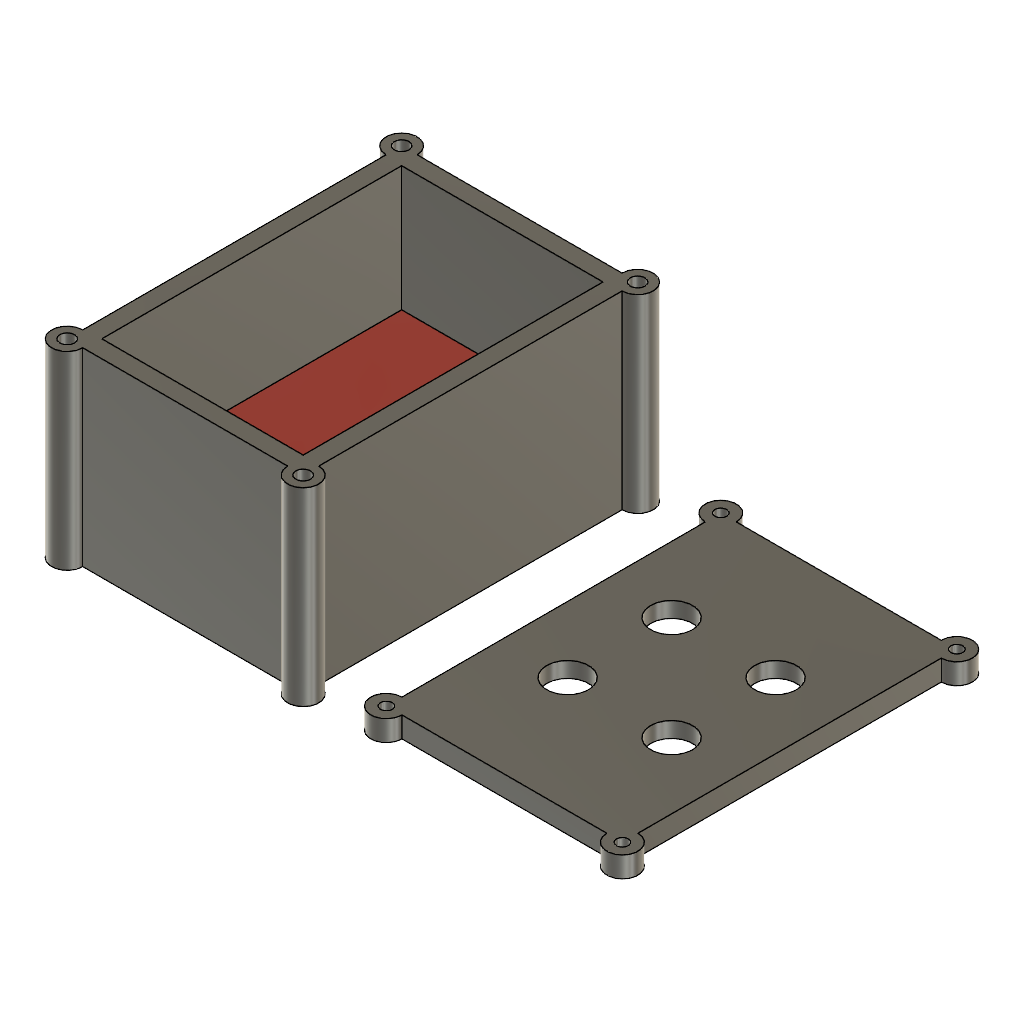
TP2 Caja (Autodesk Fusion 360 design; units mm, degrees)
Autodesk Fusion 360 part; units mm, degrees
sketch "Boceto1" plane through (0, 0, 0) normal (0, 0, 1) x (1, 0, 0)
  line L0 (0, 0) -> (56.1, 0)
  line L1 (56.1, 0) -> (56.1, 84.5)
  line L2 (56.1, 84.5) -> (0, 84.5)
  line L3 (0, 84.5) -> (0, 0)
  dimension "d1" = 56.1
  dimension "d2" = 84.5
  constraint horizontal L0
  constraint vertical L1
  constraint horizontal L2
  constraint vertical L3
  constraint coincident L0.start L3.end
  measures "d1" distance of L0.start L0.end
  measures "d2" distance of L0.start L2.end
extrude "Extruir1" add sketch "Boceto1" along normal blind 16.7 makes body 1
sketch "Boceto2" plane through (0, 0, 0) normal (0, 0, 1) x (1, 0, 0)
sketch "Boceto23" plane through (0, 0, 0) normal (0, 0, 1) x (1, 0, 0)
  line L0 (-6, -6) -> (62.1, -6)
  line L1 (62.1, -6) -> (62.1, 90.5)
  line L2 (62.1, 90.5) -> (-6, 90.5)
  line L3 (-6, 90.5) -> (-6, -6)
extrude "Extruir22" add sketch "Boceto23" along normal blind 54.7 from surface at -3 separate body makes body 2
sketch "Boceto24" plane through (0, 0, 0) normal (0, 0, 1) x (1, 0, 0)
  circle A0 centre (-6, -6) radius 4.5
  circle A1 centre (62.1, -6) radius 4.5
  circle A2 centre (-6, 90.5) radius 4.5
  circle A3 centre (62.1, 90.5) radius 4.5
extrude "Extruir23" add sketch "Boceto24" along normal blind 54.7 from surface at -3 bodies 2
sketch "Boceto25" plane through (0, 0, 0) normal (0, 0, 1) x (1, 0, 0)
  line L0 (-1, -1) -> (57.1, -1)
  line L1 (57.1, -1) -> (57.1, 85.5)
  line L2 (57.1, 85.5) -> (-1, 85.5)
  line L3 (-1, 85.5) -> (-1, -1)
extrude "Extruir24" cut sketch "Boceto25" along normal blind 52.7 bodies 2
sketch "Boceto26" plane through (0, 0, 0) normal (0, 0, 1) x (1, 0, 0)
  circle A0 centre (-6, -6) radius 2.1
  circle A1 centre (62.1, -6) radius 2.1
  circle A2 centre (-6, 90.5) radius 2.1
  circle A3 centre (62.1, 90.5) radius 2.1
extrude "Extruir25" cut sketch "Boceto26" against normal blind 6 from surface at 51.7 bodies 2
ref_plane "PlanoDeObra3" through (0, 88, 0) normal (0, 1, 0) x (0, 0, 1)
sketch "Boceto27" plane through (0, 88, 0) normal (0, 1, 0) x (1, 0, 0)
  line L0 (24.05, -16.15) -> (32.05, -16.15)
  line L1 (32.05, -16.15) -> (32.05, -13.63)
  line L2 (32.05, -13.63) -> (31.25, -12.83)
  line L3 (31.25, -12.83) -> (24.85, -12.83)
  line L4 (24.85, -12.83) -> (24.05, -13.63)
  line L5 (24.05, -13.63) -> (24.05, -16.15)
extrude "Corte_MicroUSB" cut sketch "Boceto27" along normal mid plane 7 bodies 2
sketch "Boceto28" plane through (0, 0, 0) normal (0, 0, 1) x (1, 0, 0)
  line L0 (86.1, -6) -> (154.2, -6)
  line L1 (154.2, -6) -> (154.2, 90.5)
  line L2 (154.2, 90.5) -> (86.1, 90.5)
  line L3 (86.1, 90.5) -> (86.1, -6)
extrude "Extruir27" add sketch "Boceto28" along normal blind 6 separate body makes body 3
sketch "Boceto29" plane through (0, 0, 0) normal (0, 0, 1) x (1, 0, 0)
  circle A0 centre (86.1, -6) radius 4.5
  circle A1 centre (154.2, -6) radius 4.5
  circle A2 centre (86.1, 90.5) radius 4.5
  circle A3 centre (154.2, 90.5) radius 4.5
extrude "Extruir28" add sketch "Boceto29" along normal blind 6 bodies 3
sketch "Boceto30" plane through (0, 0, 0) normal (0, 0, 1) x (1, 0, 0)
  circle A0 centre (86.1, -6) radius 1.7
  circle A1 centre (154.2, -6) radius 1.7
  circle A2 centre (86.1, 90.5) radius 1.7
  circle A3 centre (154.2, 90.5) radius 1.7
extrude "Extruir29" cut sketch "Boceto30" along normal blind 6 bodies 3
sketch "Boceto31" plane through (0, 0, 0) normal (0, 0, 1) x (1, 0, 0)
  circle A0 centre (105.15, 27.25) radius 6.05
  circle A1 centre (135.15, 27.25) radius 6.05
  circle A2 centre (105.15, 57.25) radius 6.05
  circle A3 centre (135.15, 57.25) radius 6.05
extrude "Extruir30" cut sketch "Boceto31" along normal blind 6 bodies 3
sketch "Boceto32" plane through (0, 0, 0) normal (0, 0, 1) x (1, 0, 0)
  circle A0 centre (105.15, 27.25) radius 9.5
  circle A1 centre (135.15, 27.25) radius 9.5
  circle A2 centre (105.15, 57.25) radius 9.5
  circle A3 centre (135.15, 57.25) radius 9.5
extrude "Extruir31" cut sketch "Boceto32" along normal blind 1.5 bodies 3
named bodies: "EspacioOcupadoProto+Placa", "Caja_Base", "Tapa"
